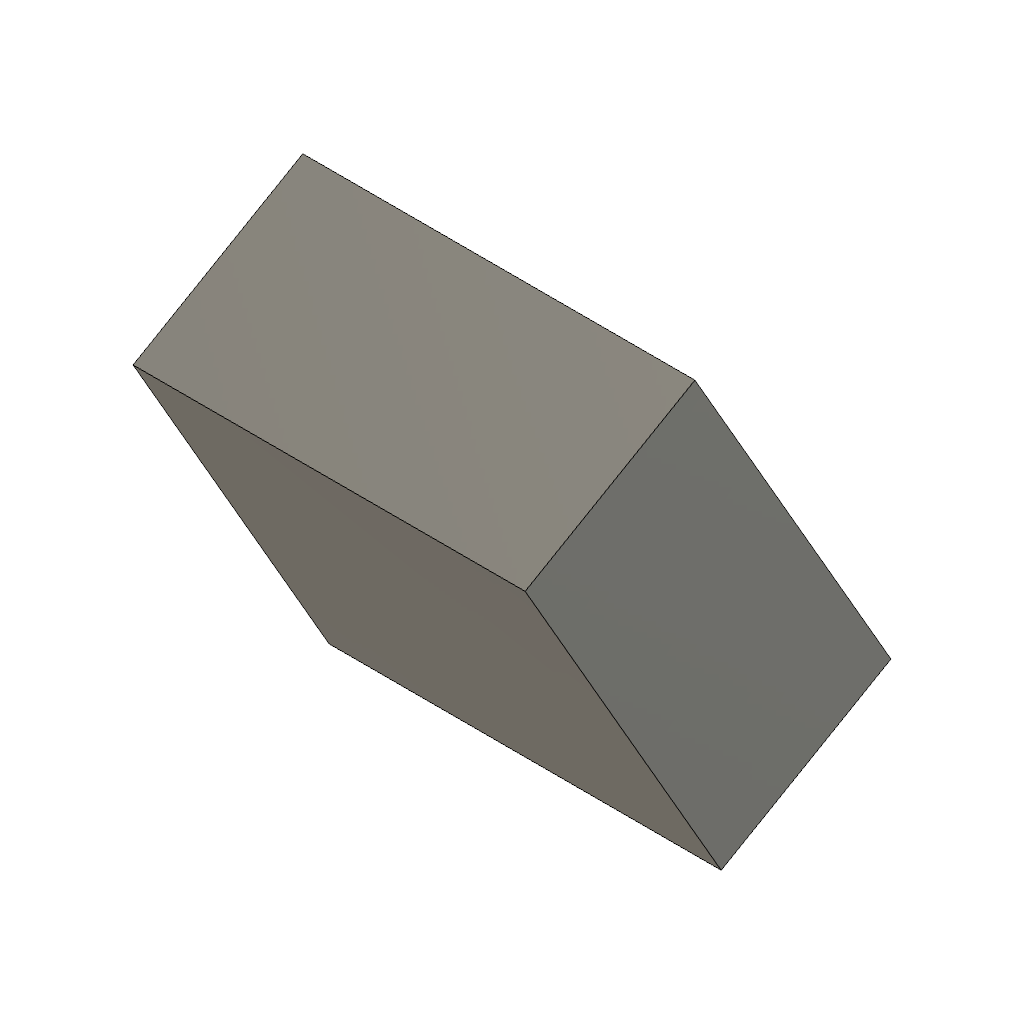
angled_rectangle_overlap (Autodesk Fusion 360 design; units mm, degrees)
part number: 2026-10-21-12-26-13-998
Autodesk Fusion 360 part; units mm, degrees
ref_plane "WorkPlane1" through (12.125, 0, 0) normal (0, -0.5, 0.866025) x (1, 0, 0)
sketch "TrimmedProfileSources" plane through (0, 0, 0) normal (0, -0.5, 0.866025) x (1, 0, 0)
  line L0 (0, 0) -> (40, 0)
  line L1 (40, 0) -> (40, 30)
  line L2 (40, 30) -> (0, 30)
  line L3 (0, 30) -> (0, 0)
  line L4 (20, -10) -> (50, -10)
  line L5 (50, -10) -> (50, 20)
  line L6 (50, 20) -> (20, 20)
  line L7 (20, 20) -> (20, -10)
extrude "SelectedTrimmedProfile" add sketch "TrimmedProfileSources" along normal blind 10 contours L0 L1 L6 L7
